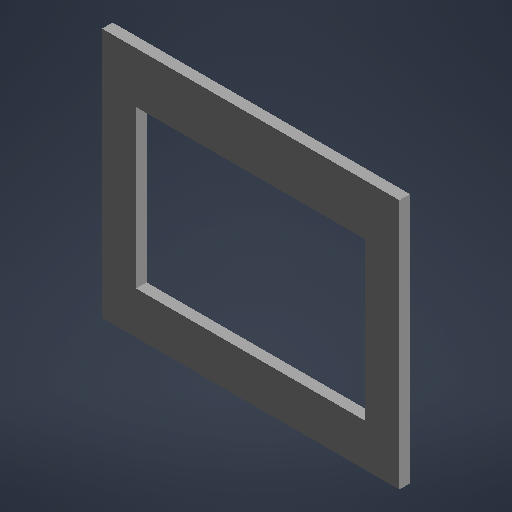
# Autodesk Inventor part: R2_tapa_torso
Saved by Autodesk Inventor 2027 (Build 310192060, 192F)
## iProperties
Part Number: R2_tapa_torso
Material: Genérico
Document SubType Name: Modelado
Designer: rodri
Appearance: Por defecto
Author: rodri
Autodesk Inventor part; units mm, degrees
ref_plane "Plano YZ" through (0, 0, 0) normal (1, 0, 0) x (0, 1, 0)
ref_plane "Plano de trabajo1" through (0, 0, 25.5) normal (0, 0, 1) x (1, 0, 0)
sketch "Boceto1" plane through (0, 0, 25.5) normal (0, 0, 1) x (1, 0, 0)
  line L0 (-35, 6.5) -> (35, 6.5)
  line L1 (35, 6.5) -> (35, 65.5)
  line L2 (35, 65.5) -> (-35, 65.5)
  line L3 (-35, 65.5) -> (-35, 6.5)
  constraints: 8 end point, 2 parallel, 1 horizontal, 1 perpendicular
extrude "Extrusión1" add sketch "Boceto1" along normal blind 2.5
ref_plane "Plano de trabajo2" through (0, 0, 25.4) normal (0, 0, 1) x (1, 0, 0)
sketch "Boceto2" plane through (0, 0, 25.4) normal (0, 0, 1) x (1, 0, 0)
  line L0 (-27, 16.5) -> (27, 16.5)
  line L1 (27, 16.5) -> (27, 53.5)
  line L2 (27, 53.5) -> (-27, 53.5)
  line L3 (-27, 53.5) -> (-27, 16.5)
  constraints: 8 end point, 2 parallel, 1 horizontal, 1 perpendicular
extrude "Extrusión2" cut sketch "Boceto2" along normal blind 2.7
